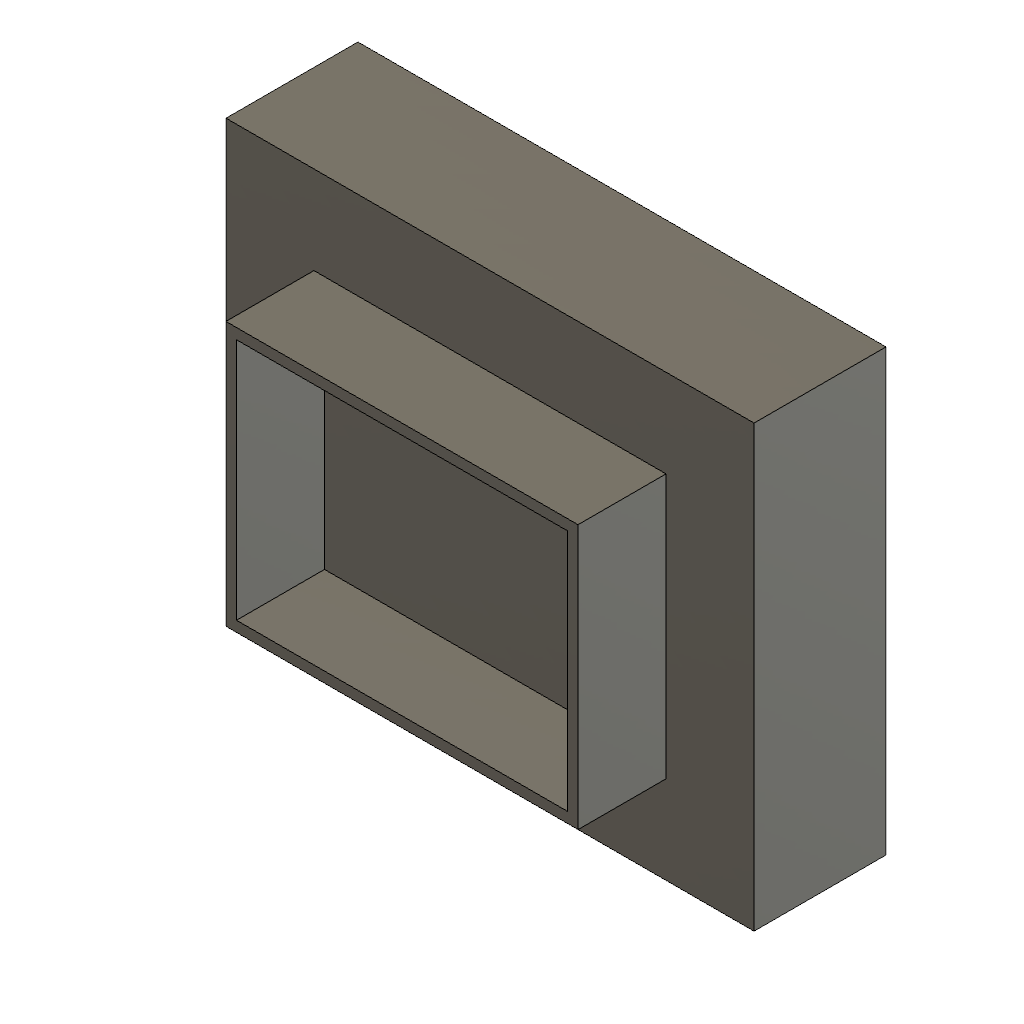
join (Autodesk Fusion 360 design; units mm, degrees)
part number: 2026-10-21-15-45-13-496
Autodesk Fusion 360 part; units mm, degrees
sketch "OwnedThinOperationBlockProfile" plane through (0, 0, 0) normal (0, 0, 1) x (1, 0, 0)
  line L0 (-10, -10) -> (50, -10)
  line L1 (50, -10) -> (50, 40)
  line L2 (50, 40) -> (-10, 40)
  line L3 (-10, 40) -> (-10, -10)
extrude "OwnedThinOperationTargetBlockExtrude" add sketch "OwnedThinOperationBlockProfile" along normal blind 15
sketch "OwnedThinOperationRingProfile" plane through (0, 0, 0) normal (0, 0, 1) x (1, 0, 0)
  line L0 (0, 0) -> (40, 0)
  line L1 (40, 0) -> (40, 30)
  line L2 (40, 30) -> (0, 30)
  line L3 (0, 30) -> (0, 0)
extrude "OwnedThinExtrudeOperation_join" add sketch "OwnedThinOperationRingProfile" along normal blind 25 thin wall 1.2 inside
named bodies: "OwnedThinOperationTarget_join"
